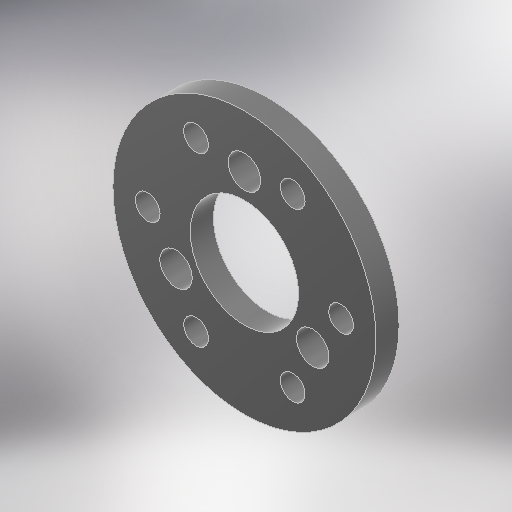
# Autodesk Inventor part: 3D_plate-spacer
Saved by Autodesk Inventor 2025.3 (Build 293356030, 356C)
## iProperties
Created: 2026-02-11
Part Number: 3D_plate-spacer
Material: 一般
Document SubType Name: Modeling
Designer: ibuki_ono
Density: 1 g/cm^3
Appearance: 滑らか - 黒
Author: ibuki_ono
## iProperties of the stored document 3D_plate-spacer_3D プリント.ipt
Created: 2026-08-06
Part Number: 3D_plate-spacer_3D プリント
Material: 一般
Document SubType Name: Modeling
Designer: ibuki_ono
Density: 1 g/cm^3
Appearance: 既定
Author: ibuki_ono
Autodesk Inventor part; units mm, degrees
ref_plane "YZ Plane" through (0, 0, 0) normal (1, 0, 0) x (0, 1, 0)
ref_plane "XZ Plane" through (0, 0, 0) normal (0, 1, 0) x (-1, 0, 0)
ref_plane "XY Plane" through (0, 0, 0) normal (0, 0, 1) x (1, 0, 0)
sketch "スケッチ1" plane through (0, 0, 0) normal (0, 0, 1) x (1, 0, 0)
  circle A0 centre (0, 0) radius 17
  dimension "d0" = 34
  constraints: 1 centre point, 1 coincident
  measures "d0" diameter of A0
extrude "押し出し1" add sketch "スケッチ1" along normal blind 3
sketch "スケッチ2" plane through (0, 0, 3) normal (0, 0, 1) x (1, 0, 0)
  line L0 (0, 0) -> (0, 10.2) construction
  line L1 (0, 0) -> (10.2, 0) construction
  dimension "d3" = 10.2
  dimension "d4" = 90
  constraints: 4 end point, 1 coincident, 1 horizontal, 1 perpendicular, 1 vertical
  measures "d3" distance of L0.start L0.end
  measures "d4" angle of L1 L0
hole "穴1" at (0, 10.2, 3) direction (0, 0, -1) diameter 4.2 end through all
pattern_circular "円形状パターン1" count 3 over 360 about axis through (0, 0, 0) along (0, 0, 1) of "穴1"
sketch "スケッチ3" plane through (0, 0, 3) normal (0, 0, 1) x (1, 0, 0)
  circle A0 centre (0, 10.2) radius 2.1 projected
  line L0 (0, 10.2) -> (0, 0) construction
  line L1 (0, 0) -> (-6.25, 10.8253) construction
  dimension "d15" = 12.5
  dimension "d16" = 30
  constraints: 4 end point, 1 coincident, 1 vertical
  measures "d15" distance of L0.end L1.end
  measures "d16" angle of L0 L1
hole "穴2" at (-6.25, 10.8253, 3) direction (0, 0, -1) diameter 3.2 end through all
pattern_circular "円形状パターン2" count 6 over 360 about axis through (0, 0, 0) along (0, 0, 1) of "穴2"
sketch "スケッチ4" plane through (0, 0, 3) normal (0, 0, 1) x (1, 0, 0)
  circle A0 centre (0, 0) radius 7
  dimension "d27" = 14
  constraints: 1 centre point, 1 coincident
  measures "d27" diameter of A0
extrude "押し出し2" cut sketch "スケッチ4" against normal through all
